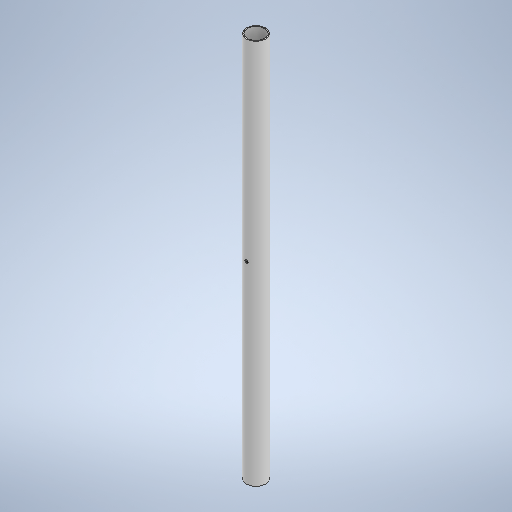
# Autodesk Inventor part: 40碳管
Saved by Autodesk Inventor 2025 (Build 290162000, 162)
## iProperties
Created: 2026-11-18
Part Number: 40碳管
Material: 常规
Document SubType Name: Modeling
Designer: ylh00
Density: 1 g/cm^3
Appearance: 默认
Author: ylh00
Autodesk Inventor part; units mm, degrees
ref_plane "YZ Plane" through (0, 0, 0) normal (1, 0, 0) x (0, 1, 0)
ref_plane "XZ Plane" through (0, 0, 0) normal (0, 1, 0) x (-1, 0, 0)
ref_plane "XY Plane" through (0, 0, 0) normal (0, 0, 1) x (1, 0, 0)
sketch "草图1" plane through (0, 0, 0) normal (0, 1, 0) x (-1, 0, 0)
  circle A0 centre (0, 0) radius 10
  circle A1 centre (0, 0) radius 9
  dimension "d0" = 20
  dimension "d1" = 18
  constraints: 2 centre point, 2 coincident
  measures "d0" diameter of A0
  measures "d1" diameter of A1
extrude "拉伸1" add sketch "草图1" along normal blind 400
sketch "草图2" plane through (0, 0, 0) normal (0, 0, 1) x (1, 0, 0)
  line L0 (-10, 0) -> (-10, 400) projected
  line L1 (-10, 200) -> (10, 200)
  line L2 (10, 0) -> (10, 400) projected
  circle A0 centre (0, 200) radius 1.6
  point P0 (0, 0)
  dimension "d4" = 3.2
  constraints: 3 midpoint, 2 end point, 1 centre point
  measures "d4" diameter of A0
extrude "拉伸2" cut sketch "草图2" along normal mid plane 20
